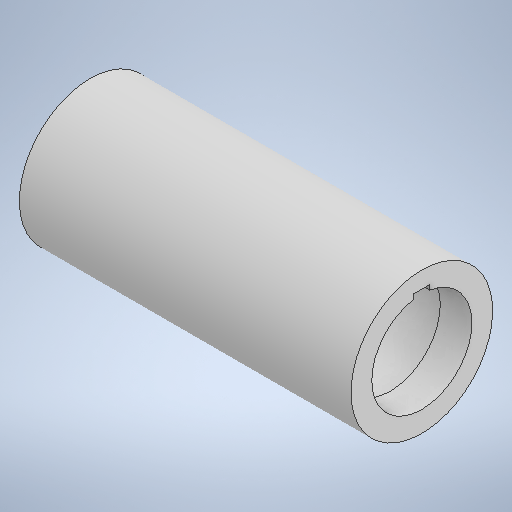
# Autodesk Inventor part: Buje
Saved by Autodesk Inventor 2025.3 (Build 293356030, 356C)
## iProperties
Created: 2025-08-17
Part Number: Buje
Material: Generic
Document SubType Name: Modeling
Designer: PC
Density: 1 g/cm^3
Appearance: Default
Author: PC
Autodesk Inventor part; units mm, degrees
ref_plane "YZ Plane" through (0, 0, 0) normal (1, 0, 0) x (0, 1, 0)
ref_plane "XZ Plane" through (0, 0, 0) normal (0, 1, 0) x (-1, 0, 0)
sketch "Sketch1" plane through (0, 0, 0) normal (1, 0, 0) x (0, 1, 0)
  circle A0 centre (0, 0) radius 13.45
  circle A1 centre (0, 0) radius 9.5
  dimension "d0" = 26.9
  dimension "d1" = 19
  constraints: 2 centre point, 2 coincident
  measures "d0" diameter of A0
  measures "d1" diameter of A1
extrude "Extrusion1" add sketch "Sketch1" along normal mid plane 63
ref_plane "Work Plane1" through (21.5, 0, 0) normal (1, 0, 0) x (0, 0, -1)
sketch "Sketch2" plane through (21.5, 0, 0) normal (1, 0, 0) x (0, 0, -1)
  circle A0 centre (0, 0) radius 9.9
  circle A1 centre (0, 0) radius 9.5 projected
  dimension "d5" = 19.8
  constraints: 1 centre point, 1 coincident
  measures "d5" diameter of A0
extrude "Extrusion2" cut sketch "Sketch2" along normal mid plane 8
sketch "Sketch3" plane through (31.5, 0, 0) normal (1, 0, 0) x (0, 0, -1)
  line L0 (-1.5, 9.3808) -> (-1.5, 10.3)
  line L1 (-1.5, 10.3) -> (1.5, 10.3)
  line L2 (1.5, 10.3) -> (1.5, 9.3808)
  circle A0 centre (0, 0) radius 9.5 projected
  dimension "d8" = 3
  dimension "d9" = 1.5
  dimension "d10" = 10.3
  constraints: 6 end point, 2 perpendicular, 2 point on circle, 1 vertical
  measures "d8" distance of L0.end L1.end
  measures "d9" distance from line of A0.centre L2
  measures "d10" distance from line of A0.centre L1
extrude "Extrusion3" cut sketch "Sketch3" against normal through all contours L0 L1 L2 A0
body "Solid1"
